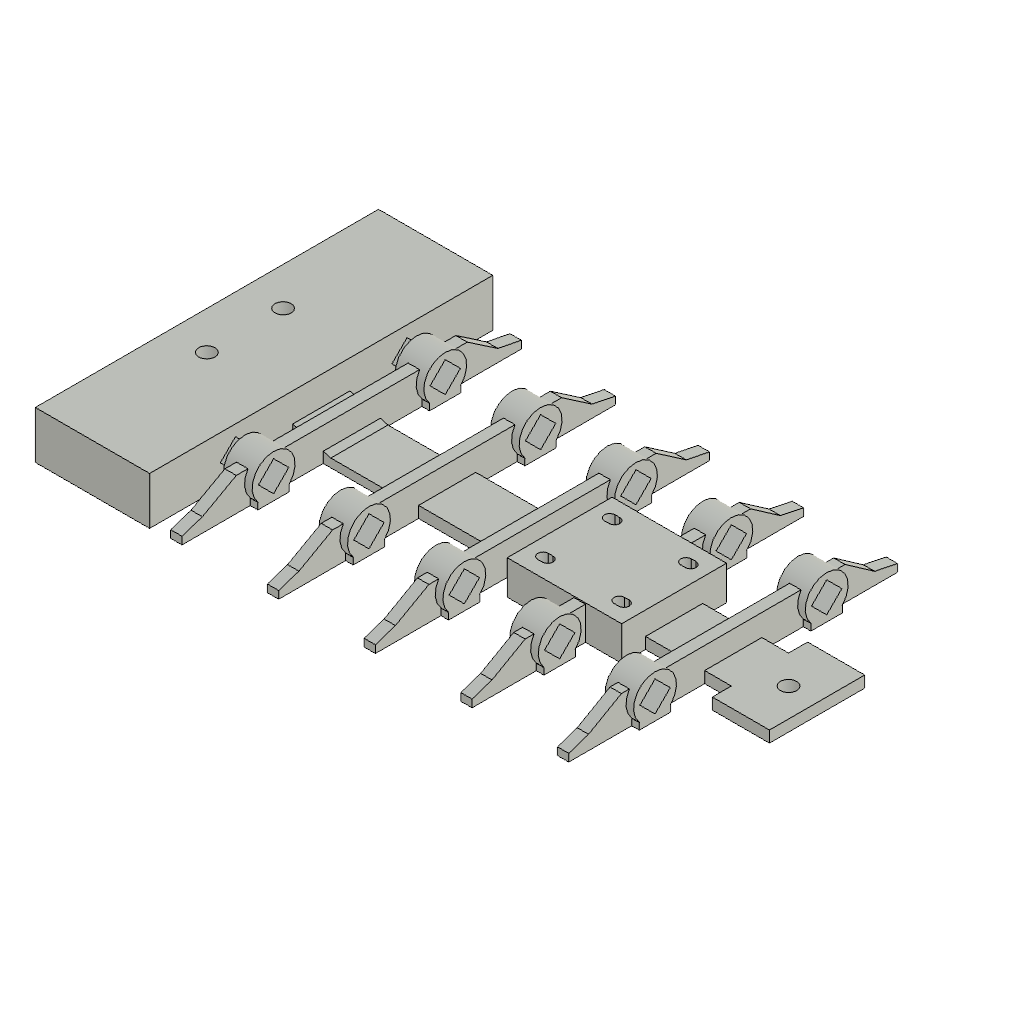
wing_root (Autodesk Fusion 360 design; units mm, degrees)
part number: 2026-10-10-17-06-17-564
Autodesk Fusion 360 part; units mm, degrees
sketch "Continuous connecting strip sketch" plane through (0, 0, 0) normal (0, 0, 1) x (1, 0, 0)
  line L0 (23.95, -6) -> (128, -6)
  line L1 (128, -6) -> (128, 6)
  line L2 (128, 6) -> (23.95, 6)
  line L3 (23.95, 6) -> (23.95, -6)
extrude "Continuous connecting strip" add sketch "Continuous connecting strip sketch" along normal blind 1.8
sketch "Root tongue sketch" plane through (0, 0, 0) normal (0, 0, 1) x (1, 0, 0)
  line L0 (0, -36) -> (24, -36)
  line L1 (24, -36) -> (24, 36)
  line L2 (24, 36) -> (0, 36)
  line L3 (0, 36) -> (0, -36)
extrude "Root tongue" add sketch "Root tongue sketch" along normal blind 10
sketch "Reinforced strip beyond gauge sketch" plane through (0, 0, 0) normal (0, 0, 1) x (1, 0, 0)
  line L0 (48, -6) -> (128, -6)
  line L1 (128, -6) -> (128, 6)
  line L2 (128, 6) -> (48, 6)
  line L3 (48, 6) -> (48, -6)
extrude "Reinforced strip beyond gauge" add sketch "Reinforced strip beyond gauge sketch" along normal blind 2.4
sketch "Root gauge shoulder sketch" plane through (0, 0, 0) normal (0, 1, 0) x (1, 0, 0)
  line L0 (23.95, 0) -> (32, 0)
  line L1 (32, 0) -> (32, -1.8)
  line L2 (32, -1.8) -> (23.95, -4)
  line L3 (23.95, -4) -> (23.95, 0)
extrude "Root tapered gauge shoulder" add sketch "Root gauge shoulder sketch" along normal mid plane 12
ref_plane "WorkPlane1" through (28, 0, 0) normal (1, 0, 0) x (0, 1, 0)
sketch "Rib at 28 mm sketch" plane through (28, 0, 0) normal (1, 0, 0) x (0, 0, -1)
  line L0 (0, -35.6072) -> (0, 35.6072)
  line L1 (0, 35.6072) -> (-1.6, 35.6072)
  line L2 (-1.6, 35.6072) -> (-2.6, 30.6222)
  line L3 (-2.6, 30.6222) -> (-6.95, 24.2129)
  line L4 (-6.95, 24.2129) -> (-6.95, -24.2129)
  line L5 (-6.95, -24.2129) -> (-3, -31.3343)
  line L6 (-3, -31.3343) -> (-1.6, -35.6072)
  line L7 (-1.6, -35.6072) -> (0, -35.6072)
extrude "Rib at 28 mm" add sketch "Rib at 28 mm sketch" along normal blind 2.4
ref_plane "WorkPlane2" through (26, 0, 0) normal (1, 0, 0) x (0, 1, 0)
sketch "front short guide at 28 mm sketch" plane through (26, 0, 0) normal (1, 0, 0) x (0, 0, -1)
  circle A0 centre (-4.5, -18) radius 4.5
extrude "front short guide at 28 mm" add sketch "front short guide at 28 mm sketch" along normal blind 6
sketch "front guide foot at 28 mm sketch" plane through (0, 0, 0) normal (0, 0, 1) x (1, 0, 0)
  line L0 (26, -21.3) -> (32, -21.3)
  line L1 (32, -21.3) -> (32, -14.7)
  line L2 (32, -14.7) -> (26, -14.7)
  line L3 (26, -14.7) -> (26, -21.3)
extrude "front guide foot at 28 mm" add sketch "front guide foot at 28 mm sketch" along normal blind 1.4
ref_plane "WorkPlane3" through (26, 0, 0) normal (1, 0, 0) x (0, 1, 0)
sketch "rear short guide at 28 mm sketch" plane through (26, 0, 0) normal (1, 0, 0) x (0, 0, -1)
  circle A0 centre (-4.5, 18) radius 4.5
extrude "rear short guide at 28 mm" add sketch "rear short guide at 28 mm sketch" along normal blind 6
sketch "rear guide foot at 28 mm sketch" plane through (0, 0, 0) normal (0, 0, 1) x (1, 0, 0)
  line L0 (26, 14.7) -> (32, 14.7)
  line L1 (32, 14.7) -> (32, 21.3)
  line L2 (32, 21.3) -> (26, 21.3)
  line L3 (26, 21.3) -> (26, 14.7)
extrude "rear guide foot at 28 mm" add sketch "rear guide foot at 28 mm sketch" along normal blind 1.4
ref_plane "WorkPlane4" through (48, 0, 0) normal (1, 0, 0) x (0, 1, 0)
sketch "Rib at 48 mm sketch" plane through (48, 0, 0) normal (1, 0, 0) x (0, 0, -1)
  line L0 (0, -35.3266) -> (0, 35.3266)
  line L1 (0, 35.3266) -> (-1.6, 35.3266)
  line L2 (-1.6, 35.3266) -> (-2.6, 30.3809)
  line L3 (-2.6, 30.3809) -> (-6.95, 24.0221)
  line L4 (-6.95, 24.0221) -> (-6.95, -24.0221)
  line L5 (-6.95, -24.0221) -> (-3, -31.0874)
  line L6 (-3, -31.0874) -> (-1.6, -35.3266)
  line L7 (-1.6, -35.3266) -> (0, -35.3266)
extrude "Rib at 48 mm" add sketch "Rib at 48 mm sketch" along normal blind 2.4
ref_plane "WorkPlane5" through (46, 0, 0) normal (1, 0, 0) x (0, 1, 0)
sketch "front short guide at 48 mm sketch" plane through (46, 0, 0) normal (1, 0, 0) x (0, 0, -1)
  circle A0 centre (-4.5, -18) radius 4.5
extrude "front short guide at 48 mm" add sketch "front short guide at 48 mm sketch" along normal blind 6
sketch "front guide foot at 48 mm sketch" plane through (0, 0, 0) normal (0, 0, 1) x (1, 0, 0)
  line L0 (46, -21.3) -> (52, -21.3)
  line L1 (52, -21.3) -> (52, -14.7)
  line L2 (52, -14.7) -> (46, -14.7)
  line L3 (46, -14.7) -> (46, -21.3)
extrude "front guide foot at 48 mm" add sketch "front guide foot at 48 mm sketch" along normal blind 1.4
ref_plane "WorkPlane6" through (46, 0, 0) normal (1, 0, 0) x (0, 1, 0)
sketch "rear short guide at 48 mm sketch" plane through (46, 0, 0) normal (1, 0, 0) x (0, 0, -1)
  circle A0 centre (-4.5, 18) radius 4.5
extrude "rear short guide at 48 mm" add sketch "rear short guide at 48 mm sketch" along normal blind 6
sketch "rear guide foot at 48 mm sketch" plane through (0, 0, 0) normal (0, 0, 1) x (1, 0, 0)
  line L0 (46, 14.7) -> (52, 14.7)
  line L1 (52, 14.7) -> (52, 21.3)
  line L2 (52, 21.3) -> (46, 21.3)
  line L3 (46, 21.3) -> (46, 14.7)
extrude "rear guide foot at 48 mm" add sketch "rear guide foot at 48 mm sketch" along normal blind 1.4
ref_plane "WorkPlane7" through (68, 0, 0) normal (1, 0, 0) x (0, 1, 0)
sketch "Rib at 68 mm sketch" plane through (68, 0, 0) normal (1, 0, 0) x (0, 0, -1)
  line L0 (0, -35.046) -> (0, 35.046)
  line L1 (0, 35.046) -> (-1.6, 35.046)
  line L2 (-1.6, 35.046) -> (-2.6, 30.1396)
  line L3 (-2.6, 30.1396) -> (-6.95, 23.8313)
  line L4 (-6.95, 23.8313) -> (-6.95, -23.8313)
  line L5 (-6.95, -23.8313) -> (-3, -30.8405)
  line L6 (-3, -30.8405) -> (-1.6, -35.046)
  line L7 (-1.6, -35.046) -> (0, -35.046)
extrude "Rib at 68 mm" add sketch "Rib at 68 mm sketch" along normal blind 2.4
ref_plane "WorkPlane8" through (66, 0, 0) normal (1, 0, 0) x (0, 1, 0)
sketch "front short guide at 68 mm sketch" plane through (66, 0, 0) normal (1, 0, 0) x (0, 0, -1)
  circle A0 centre (-4.5, -18) radius 4.5
extrude "front short guide at 68 mm" add sketch "front short guide at 68 mm sketch" along normal blind 6
sketch "front guide foot at 68 mm sketch" plane through (0, 0, 0) normal (0, 0, 1) x (1, 0, 0)
  line L0 (66, -21.3) -> (72, -21.3)
  line L1 (72, -21.3) -> (72, -14.7)
  line L2 (72, -14.7) -> (66, -14.7)
  line L3 (66, -14.7) -> (66, -21.3)
extrude "front guide foot at 68 mm" add sketch "front guide foot at 68 mm sketch" along normal blind 1.4
ref_plane "WorkPlane9" through (66, 0, 0) normal (1, 0, 0) x (0, 1, 0)
sketch "rear short guide at 68 mm sketch" plane through (66, 0, 0) normal (1, 0, 0) x (0, 0, -1)
  circle A0 centre (-4.5, 18) radius 4.5
extrude "rear short guide at 68 mm" add sketch "rear short guide at 68 mm sketch" along normal blind 6
sketch "rear guide foot at 68 mm sketch" plane through (0, 0, 0) normal (0, 0, 1) x (1, 0, 0)
  line L0 (66, 14.7) -> (72, 14.7)
  line L1 (72, 14.7) -> (72, 21.3)
  line L2 (72, 21.3) -> (66, 21.3)
  line L3 (66, 21.3) -> (66, 14.7)
extrude "rear guide foot at 68 mm" add sketch "rear guide foot at 68 mm sketch" along normal blind 1.4
ref_plane "WorkPlane10" through (88, 0, 0) normal (1, 0, 0) x (0, 1, 0)
sketch "Rib at 88 mm sketch" plane through (88, 0, 0) normal (1, 0, 0) x (0, 0, -1)
  line L0 (0, -34.7654) -> (0, 34.7654)
  line L1 (0, 34.7654) -> (-1.6, 34.7654)
  line L2 (-1.6, 34.7654) -> (-2.6, 29.8983)
  line L3 (-2.6, 29.8983) -> (-6.95, 23.6405)
  line L4 (-6.95, 23.6405) -> (-6.95, -23.6405)
  line L5 (-6.95, -23.6405) -> (-3, -30.5936)
  line L6 (-3, -30.5936) -> (-1.6, -34.7654)
  line L7 (-1.6, -34.7654) -> (0, -34.7654)
extrude "Rib at 88 mm" add sketch "Rib at 88 mm sketch" along normal blind 2.4
ref_plane "WorkPlane11" through (86, 0, 0) normal (1, 0, 0) x (0, 1, 0)
sketch "front short guide at 88 mm sketch" plane through (86, 0, 0) normal (1, 0, 0) x (0, 0, -1)
  circle A0 centre (-4.5, -18) radius 4.5
extrude "front short guide at 88 mm" add sketch "front short guide at 88 mm sketch" along normal blind 6
sketch "front guide foot at 88 mm sketch" plane through (0, 0, 0) normal (0, 0, 1) x (1, 0, 0)
  line L0 (86, -21.3) -> (92, -21.3)
  line L1 (92, -21.3) -> (92, -14.7)
  line L2 (92, -14.7) -> (86, -14.7)
  line L3 (86, -14.7) -> (86, -21.3)
extrude "front guide foot at 88 mm" add sketch "front guide foot at 88 mm sketch" along normal blind 1.4
ref_plane "WorkPlane12" through (86, 0, 0) normal (1, 0, 0) x (0, 1, 0)
sketch "rear short guide at 88 mm sketch" plane through (86, 0, 0) normal (1, 0, 0) x (0, 0, -1)
  circle A0 centre (-4.5, 18) radius 4.5
extrude "rear short guide at 88 mm" add sketch "rear short guide at 88 mm sketch" along normal blind 6
sketch "rear guide foot at 88 mm sketch" plane through (0, 0, 0) normal (0, 0, 1) x (1, 0, 0)
  line L0 (86, 14.7) -> (92, 14.7)
  line L1 (92, 14.7) -> (92, 21.3)
  line L2 (92, 21.3) -> (86, 21.3)
  line L3 (86, 21.3) -> (86, 14.7)
extrude "rear guide foot at 88 mm" add sketch "rear guide foot at 88 mm sketch" along normal blind 1.4
ref_plane "WorkPlane13" through (108, 0, 0) normal (1, 0, 0) x (0, 1, 0)
sketch "Rib at 108 mm sketch" plane through (108, 0, 0) normal (1, 0, 0) x (0, 0, -1)
  line L0 (0, -34.4848) -> (0, 34.4848)
  line L1 (0, 34.4848) -> (-1.6, 34.4848)
  line L2 (-1.6, 34.4848) -> (-2.6, 29.657)
  line L3 (-2.6, 29.657) -> (-6.95, 23.4497)
  line L4 (-6.95, 23.4497) -> (-6.95, -23.4497)
  line L5 (-6.95, -23.4497) -> (-3, -30.3467)
  line L6 (-3, -30.3467) -> (-1.6, -34.4848)
  line L7 (-1.6, -34.4848) -> (0, -34.4848)
extrude "Rib at 108 mm" add sketch "Rib at 108 mm sketch" along normal blind 2.4
ref_plane "WorkPlane14" through (106, 0, 0) normal (1, 0, 0) x (0, 1, 0)
sketch "front short guide at 108 mm sketch" plane through (106, 0, 0) normal (1, 0, 0) x (0, 0, -1)
  circle A0 centre (-4.5, -18) radius 4.5
extrude "front short guide at 108 mm" add sketch "front short guide at 108 mm sketch" along normal blind 6
sketch "front guide foot at 108 mm sketch" plane through (0, 0, 0) normal (0, 0, 1) x (1, 0, 0)
  line L0 (106, -21.3) -> (112, -21.3)
  line L1 (112, -21.3) -> (112, -14.7)
  line L2 (112, -14.7) -> (106, -14.7)
  line L3 (106, -14.7) -> (106, -21.3)
extrude "front guide foot at 108 mm" add sketch "front guide foot at 108 mm sketch" along normal blind 1.4
ref_plane "WorkPlane15" through (106, 0, 0) normal (1, 0, 0) x (0, 1, 0)
sketch "rear short guide at 108 mm sketch" plane through (106, 0, 0) normal (1, 0, 0) x (0, 0, -1)
  circle A0 centre (-4.5, 18) radius 4.5
extrude "rear short guide at 108 mm" add sketch "rear short guide at 108 mm sketch" along normal blind 6
sketch "rear guide foot at 108 mm sketch" plane through (0, 0, 0) normal (0, 0, 1) x (1, 0, 0)
  line L0 (106, 14.7) -> (112, 14.7)
  line L1 (112, 14.7) -> (112, 21.3)
  line L2 (112, 21.3) -> (106, 21.3)
  line L3 (106, 21.3) -> (106, 14.7)
extrude "rear guide foot at 108 mm" add sketch "rear guide foot at 108 mm sketch" along normal blind 1.4
sketch "Joint landing at 116.0 sketch" plane through (0, 0, 0) normal (0, 0, 1) x (1, 0, 0)
  line L0 (116, -10) -> (128, -10)
  line L1 (128, -10) -> (128, 10)
  line L2 (128, 10) -> (116, 10)
  line L3 (116, 10) -> (116, -10)
extrude "Joint landing at 116.0" add sketch "Joint landing at 116.0 sketch" along normal blind 2.4
ref_plane "WorkPlane16" through (0, 0, -0.05) normal (0, 0, 1) x (1, 0, 0)
sketch "Joint bolt at 122.0 sketch" plane through (0, 0, -0.05) normal (0, 0, 1) x (1, 0, 0)
  circle A0 centre (122, 0) radius 1.7
  dimension "d102" = 3.4
  measures "d102" diameter of A0
extrude "Joint bolt at 122.0" cut sketch "Joint bolt at 122.0 sketch" along normal blind 2.5
sketch "MPU strap landing sketch" plane through (0, 0, 0) normal (0, 0, 1) x (1, 0, 0)
  line L0 (74, -11) -> (98, -11)
  line L1 (98, -11) -> (98, 11)
  line L2 (98, 11) -> (74, 11)
  line L3 (74, 11) -> (74, -11)
extrude "MPU strap landing" add sketch "MPU strap landing sketch" along normal blind 7.2
ref_plane "WorkPlane17" through (0, 0, -0.05) normal (0, 0, 1) x (1, 0, 0)
sketch "Root registration -8 sketch" plane through (0, 0, -0.05) normal (0, 0, 1) x (1, 0, 0)
  circle A0 centre (8, -8) radius 1.7
  dimension "d109" = 3.4
  measures "d109" diameter of A0
extrude "Root registration -8" cut sketch "Root registration -8 sketch" along normal blind 10.1
ref_plane "WorkPlane18" through (0, 0, -0.05) normal (0, 0, 1) x (1, 0, 0)
sketch "Root registration 8 sketch" plane through (0, 0, -0.05) normal (0, 0, 1) x (1, 0, 0)
  circle A0 centre (8, 8) radius 1.7
  dimension "d114" = 3.4
  measures "d114" diameter of A0
extrude "Root registration 8" cut sketch "Root registration 8 sketch" along normal blind 10.1
ref_plane "WorkPlane19" through (0, 0, -0.05) normal (0, 0, 1) x (1, 0, 0)
sketch "Board tie 78 -7 sketch" plane through (0, 0, -0.05) normal (0, 0, 1) x (1, 0, 0)
  arc A0 (77.5, -5.9) -> (77.5, -8.1) centre (77.5, -7) ccw
  line L0 (77.5, -5.9) -> (78.5, -5.9)
  arc A1 (78.5, -8.1) -> (78.5, -5.9) centre (78.5, -7) ccw
  line L1 (78.5, -8.1) -> (77.5, -8.1)
extrude "Board tie 78 -7" cut sketch "Board tie 78 -7 sketch" along normal blind 7.3
ref_plane "WorkPlane20" through (0, 0, -0.05) normal (0, 0, 1) x (1, 0, 0)
sketch "Board tie 78 7 sketch" plane through (0, 0, -0.05) normal (0, 0, 1) x (1, 0, 0)
  arc A0 (77.5, 8.1) -> (77.5, 5.9) centre (77.5, 7) ccw
  line L0 (77.5, 8.1) -> (78.5, 8.1)
  arc A1 (78.5, 5.9) -> (78.5, 8.1) centre (78.5, 7) ccw
  line L1 (78.5, 5.9) -> (77.5, 5.9)
extrude "Board tie 78 7" cut sketch "Board tie 78 7 sketch" along normal blind 7.3
ref_plane "WorkPlane21" through (0, 0, -0.05) normal (0, 0, 1) x (1, 0, 0)
sketch "Board tie 94 -7 sketch" plane through (0, 0, -0.05) normal (0, 0, 1) x (1, 0, 0)
  arc A0 (93.5, -5.9) -> (93.5, -8.1) centre (93.5, -7) ccw
  line L0 (93.5, -5.9) -> (94.5, -5.9)
  arc A1 (94.5, -8.1) -> (94.5, -5.9) centre (94.5, -7) ccw
  line L1 (94.5, -8.1) -> (93.5, -8.1)
extrude "Board tie 94 -7" cut sketch "Board tie 94 -7 sketch" along normal blind 7.3
ref_plane "WorkPlane22" through (0, 0, -0.05) normal (0, 0, 1) x (1, 0, 0)
sketch "Board tie 94 7 sketch" plane through (0, 0, -0.05) normal (0, 0, 1) x (1, 0, 0)
  arc A0 (93.5, 8.1) -> (93.5, 5.9) centre (93.5, 7) ccw
  line L0 (93.5, 8.1) -> (94.5, 8.1)
  arc A1 (94.5, 5.9) -> (94.5, 8.1) centre (94.5, 7) ccw
  line L1 (94.5, 5.9) -> (93.5, 5.9)
extrude "Board tie 94 7" cut sketch "Board tie 94 7 sketch" along normal blind 7.3
ref_plane "WorkPlane23" through (-0.05, 0, 0) normal (1, 0, 0) x (0, 1, 0)
sketch "front diamond bamboo passage sketch" plane through (-0.05, 0, 0) normal (1, 0, 0) x (0, 0, -1)
  line L0 (-4.5, -21.182) -> (-1.318, -18)
  line L1 (-1.318, -18) -> (-4.5, -14.818)
  line L2 (-4.5, -14.818) -> (-7.682, -18)
  line L3 (-7.682, -18) -> (-4.5, -21.182)
  line L4 (-4.5, -21.182) -> (-4.5, -14.818) construction
  line L5 (-1.318, -18) -> (-7.682, -18) construction
  point P0 (-4.5, -18)
  dimension "d135" = 6.364
  constraint vertical L4
  constraint horizontal L5
  constraint midpoint L4 P0
  constraint midpoint L5 P0
  constraint equal L4 L5
  measures "d135" distance of L0.end L2.end
extrude "front diamond bamboo passage" cut sketch "front diamond bamboo passage sketch" along normal blind 128.1
ref_plane "WorkPlane24" through (-0.05, 0, 0) normal (1, 0, 0) x (0, 1, 0)
sketch "rear diamond bamboo passage sketch" plane through (-0.05, 0, 0) normal (1, 0, 0) x (0, 0, -1)
  line L0 (-4.5, 14.818) -> (-1.318, 18)
  line L1 (-1.318, 18) -> (-4.5, 21.182)
  line L2 (-4.5, 21.182) -> (-7.682, 18)
  line L3 (-7.682, 18) -> (-4.5, 14.818)
  line L4 (-4.5, 14.818) -> (-4.5, 21.182) construction
  line L5 (-1.318, 18) -> (-7.682, 18) construction
  point P0 (-4.5, 18)
  dimension "d140" = 6.364
  constraint vertical L4
  constraint horizontal L5
  constraint midpoint L4 P0
  constraint midpoint L5 P0
  constraint equal L4 L5
  measures "d140" distance of L0.end L2.end
extrude "rear diamond bamboo passage" cut sketch "rear diamond bamboo passage sketch" along normal blind 128.1
equation "d10 = gaugeBeamThickness"
equation "d12 = rootThickness"
equation "d14 = spanStripThickness"
equation "d98 = spanStripThickness"
equation "d102 = m3Clearance"
equation "d105 = mpuPadThickness"
equation "d109 = m3Clearance"
equation "d114 = m3Clearance"
equation "d135 = sparBore * sqrt(2)"
equation "d140 = sparBore * sqrt(2)"
equation "sparDiameter = 4 mm" comment "Nominal bamboo diameter; choose clearance with fit coupon"
equation "sparClearance = 0.5 mm" comment "Diametral clearance; 4.5 mm coupon fit selected by user"
equation "sparBore = sparDiameter + sparClearance" comment "Flat-to-flat width of all six native diamond passages"
equation "m3Clearance = 3.4 mm" comment "Root registration and tip adapter holes"
equation "rootThickness = 10 mm" comment "Root tongue extrusion; reposition cap if changed"
equation "gaugeBeamThickness = 1.8 mm" comment "Root gauge zone; physical response needs testing"
equation "spanStripThickness = 2.4 mm" comment "Middle, tip and reinforced joint-end thickness"
equation "mpuPadThickness = 7.2 mm" comment "Raised pad clears the 6.95 mm rib tops"
named bodies: "wing_root - printable solid"
